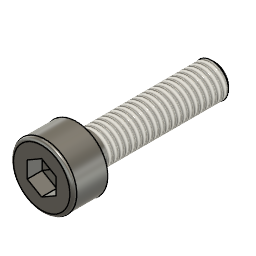
Cube_v2 (Autodesk Fusion 360 archive; units mm, degrees)
design "Hexagon Socket Head Cap Screw ISO 4762 - M3 x 12 Steel 4.6 Plain"
description: Hexagon Socket Head Cap Screw ISO 4762 - M3 x 12
part number: ISO 4762 - M3 x 12 Steel 4.6 Plain
Autodesk Fusion 360 part; units mm, degrees
(part 1 of 2)
sketch "Sketch1" plane through (0, 0, 0) normal (0, 1, 0) x (1, 0, 0)
  line L0 (-1.5, 0) -> (-1.5, 12)
  line L1 (-1.5, 12) -> (0, 12)
  line L2 (0, 12) -> (0, -3)
  line L3 (-1.5, 0) -> (-2.75, 0)
  line L4 (-2.75, 0) -> (-2.75, -3)
  line L5 (-2.75, -3) -> (0, -3)
  dimension "d9" = 3
  dimension "d106" = 3
  dimension "d107" = 12
  dimension "d116" = 5.5
  constraint perpendicular L0 L1
  constraint collinear origin L1.end L2.end
  constraint perpendicular L0 L3
  constraint coincident origin L3
  constraint vertical L2
  constraint coincident L2 L5.end
  constraint perpendicular L2 L5
  measures "d106" distance of L3 L5
  measures "d107" distance of origin L1
revolve "Revolve1" add sketch "Sketch1" angle 360 about axis through (0, 0, -12) along (0, 0, 1)
ref_plane "WorkPlane1" through (0, 0, 3) normal (0, 0, 1) x (1, 0, 0)
sketch "Sketch6" plane through (0, 0, 3) normal (0, 0, 1) x (1, 0, 0)
  line L0 (-1.25, 0.7217) -> (-1.25, -0.7217)
  line L1 (-1.25, -0.7217) -> (0, -1.4434)
  line L2 (0, -1.4434) -> (1.25, -0.7217)
  line L3 (1.25, -0.7217) -> (1.25, 0.7217)
  line L4 (1.25, 0.7217) -> (0, 1.4434)
  line L5 (0, 1.4434) -> (-1.25, 0.7217)
  dimension "d117" = 2.5
  constraint vertical L0
  measures "d117" distance of L0 L3
extrude "Extrude1" cut sketch "Sketch6" against normal blind 1.3
extrude "Extrude2" cut 1 faces at (-0.4167, 0.2406, 1.7) along direction (0, 0, -1) blind 1.3 draft -85
fillet "Fillet4" radius 0.3 1 edges at (-2.5639, 0.9944, 3)
thread "Thread3" "ISO Metric profile 3.0 M3x0.5 M3x0.5 6g" major diameter 2.927 minor diameter 2.3555 pitch 0.5 angle 60 resizes the face on face at (-1.4981, 0.0748, -8) from (0, 0, -1.25) to (0, 0, -12)
sketch "Sketch7" plane through (0, 0, 0) normal (0, 1, 0) x (1, 0, 0)
  line L0 (-1.53, 12) -> (-1.53, 11.7)
  line L1 (-1.53, 11.7) -> (-1.23, 12)
  line L2 (0, 12) -> (0, -3)
  line L3 (-1.53, 12) -> (0, 12)
  dimension "d101" = 45
  dimension "d112" = 0.3
  dimension "d113" = 1.53
  constraint coincident L2.start L3.end
  constraint perpendicular L2 L3
  constraint coincident L1.end L3
  constraint perpendicular L0 L3
  measures "d101" angle of L0 L1
  measures "d112" distance of L0.end L3
  measures "d113" distance of L0 L2.start
revolve "Revolve3" cut sketch "Sketch7" angle 360 about axis through (0, 0, 1.75) along (0, 0, 1)
equation "d9 = adsk_nomdia"
equation "adsk_nomlen = 12.00 mm"
equation "adsk_headh = 3.00 mm"
equation "adsk_headdia = 5.50 mm"
equation "adsk_nomdia = 3.00 mm"
equation "adsk_philwidth = 2.50 mm"
equation "d31 = -adsk_phildepth"
equation "adsk_phildepth = 1.30 mm"
equation "d71 = adsk_headh"
equation "d76 = -adsk_phildepth"
equation "adsk_thrlen = 10.75 mm"
equation "d86 = adsk_nomdia * 0.1"
equation "adsk_startang = 45.00 deg"
equation "d101 = adsk_startang"
equation "adsk_pitch1 = 0.50 mm"
equation "adsk_startlen = 0.30 mm"
equation "d106 = adsk_headh"
equation "d107 = adsk_nomlen"
equation "d112 = adsk_startlen"
equation "d113 = adsk_nomdia * 0.51"
equation "d115 = min(adsk_thrlen; adsk_nomlen - 0.001 mm)"
equation "d116 = adsk_headdia"
equation "d117 = adsk_philwidth"

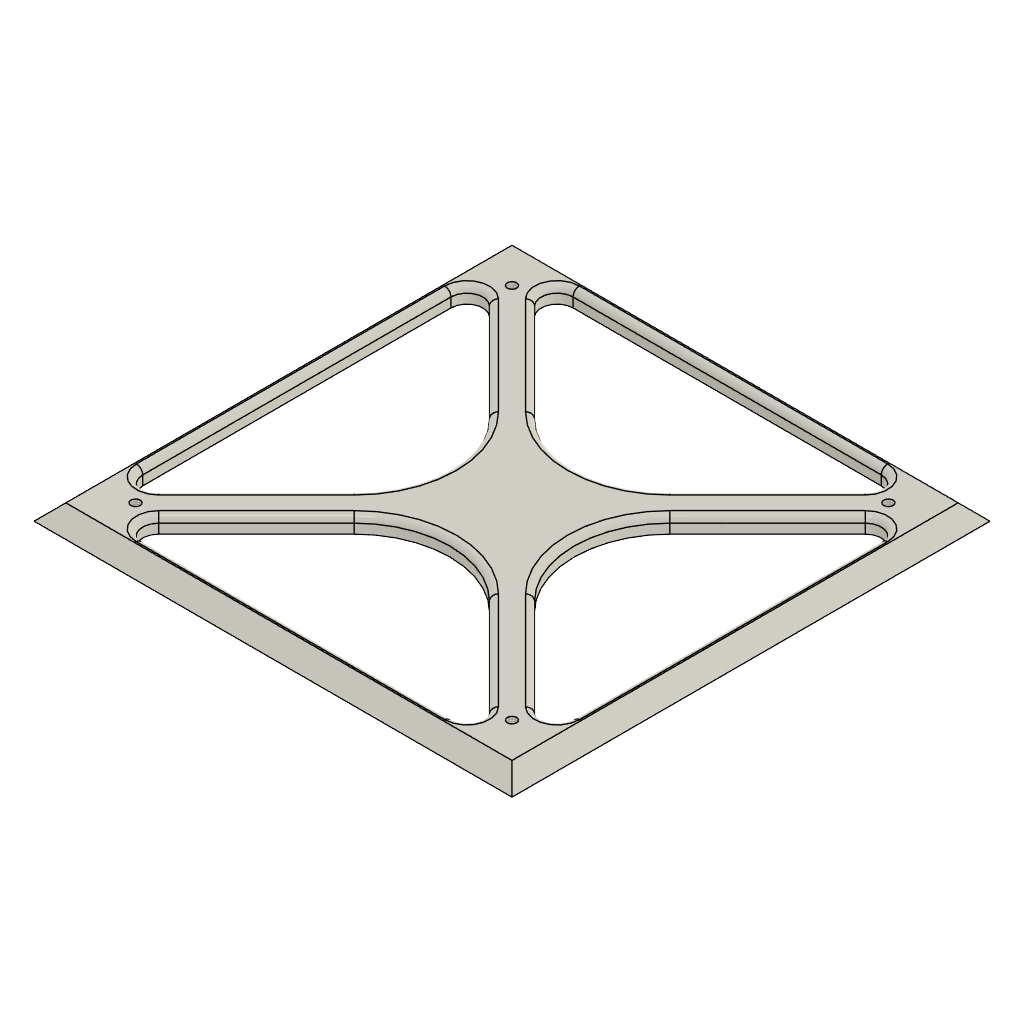
design "Cube_Bottom_Panel"
Autodesk Fusion 360 part; units mm, degrees
sketch "Sketch1" plane through (0, 0, 0) normal (0, 0, 1) x (1, 0, 0)
  line L0 (75, 75) -> (-75, 75)
  line L1 (-75, 75) -> (-75, -75)
  line L2 (-75, -75) -> (75, -75)
  line L3 (75, -75) -> (75, 75)
  line L4 (48.3579, -67.5) -> (-48.3579, -67.5)
  line L5 (-67.5, -48.3579) -> (-67.5, 48.3579)
  line L6 (-48.3579, 67.5) -> (48.3579, 67.5)
  line L7 (67.5, 48.3579) -> (67.5, -48.3579)
  line L8 (-58.9645, 51.8934) -> (-28.2843, 21.2132)
  line L9 (21.2132, -28.2843) -> (51.8934, -58.9645)
  line L10 (58.9645, -51.8934) -> (28.2843, -21.2132)
  line L11 (-21.2132, 28.2843) -> (-51.8934, 58.9645)
  line L12 (58.9645, 51.8934) -> (28.2843, 21.2132)
  line L13 (-21.2132, -28.2843) -> (-51.8934, -58.9645)
  line L14 (51.8934, 58.9645) -> (21.2132, 28.2843)
  line L15 (-28.2843, -21.2132) -> (-58.9645, -51.8934)
  arc A0 (21.2132, -28.2843) -> (-21.2132, -28.2843) centre (0, -49.4975) ccw
  arc A1 (-28.2843, -21.2132) -> (-28.2843, 21.2132) centre (-49.4975, 0) ccw
  arc A2 (-21.2132, 28.2843) -> (21.2132, 28.2843) centre (0, 49.4975) ccw
  arc A3 (28.2843, 21.2132) -> (28.2843, -21.2132) centre (49.4975, 0) ccw
  arc A4 (-48.3579, 67.5) -> (-51.8934, 58.9645) centre (-48.3579, 62.5) ccw
  arc A5 (-58.9645, 51.8934) -> (-67.5, 48.3579) centre (-62.5, 48.3579) ccw
  arc A6 (51.8934, 58.9645) -> (48.3579, 67.5) centre (48.3579, 62.5) ccw
  arc A7 (67.5, 48.3579) -> (58.9645, 51.8934) centre (62.5, 48.3579) ccw
  arc A8 (-67.5, -48.3579) -> (-58.9645, -51.8934) centre (-62.5, -48.3579) ccw
  arc A9 (-51.8934, -58.9645) -> (-48.3579, -67.5) centre (-48.3579, -62.5) ccw
  arc A10 (48.3579, -67.5) -> (51.8934, -58.9645) centre (48.3579, -62.5) ccw
  arc A11 (58.9645, -51.8934) -> (67.5, -48.3579) centre (62.5, -48.3579) ccw
  point P0 (-67.5, -67.5)
  point P1 (-67.5, 67.5)
  point P2 (67.5, 67.5)
  dimension "d1" = 150
  dimension "d2" = 150
  dimension "d3" = 135
  dimension "d4" = 135
  dimension "d9" = 30
  dimension "d10" = 30
  dimension "d11" = 30
  dimension "d12" = 30
  dimension "d13" = 5
  dimension "d14" = 5
  dimension "d15" = 5
  dimension "d16" = 5
  dimension "d17" = 5
  dimension "d18" = 5
  dimension "d19" = 5
  constraint horizontal L0
  constraint perpendicular L0 L1
  constraint parallel L0 L2
  constraint parallel L1 L3
  constraint horizontal L4
  constraint perpendicular L4 L5
  constraint parallel L4 L6
  constraint parallel L5 L7
  constraint tangent L13 A0
  constraint tangent L9 A0
  constraint tangent L15 A1
  constraint tangent L8 A1
  constraint tangent L11 A2
  constraint tangent L14 A2
  constraint tangent L10 A3
  constraint tangent L12 A3
  constraint coincident P1 L6
  constraint tangent L11 A4
  constraint tangent L6 A4
  constraint coincident P1 L5
  constraint tangent L8 A5
  constraint tangent L5 A5
  constraint coincident P2 L6
  constraint tangent L6 A6
  constraint tangent L14 A6
  constraint coincident P2 L7
  constraint tangent L12 A7
  constraint tangent L7 A7
  constraint coincident P0 L5
  constraint tangent L15 A8
  constraint tangent L5 A8
  constraint coincident P0 L4
  constraint tangent L13 A9
  constraint tangent L4 A9
  constraint equal A8 A9
  constraint tangent L4 A10
  constraint tangent L9 A10
  constraint tangent L10 A11
  constraint tangent L7 A11
  measures "d1" distance of L0.end L1.end
  measures "d2" distance of L1.end L2.end
  measures "d3" distance of P0 P1
  measures "d4" distance of P1 P2
  measures "d9" radius of A0
  measures "d10" radius of A1
  measures "d11" radius of A2
  measures "d12" radius of A3
  measures "d13" radius of A4
  measures "d14" radius of A5
  measures "d15" radius of A6
  measures "d16" radius of A7
  measures "d17" radius of A8
  measures "d18" radius of A10
  measures "d19" radius of A11
extrude "Extrude1" add sketch "Sketch1" along normal blind 5
chamfer "Chamfer1" distance 5 angle 45 4 edges at (75, 0, 5) (0, -75, 5) (-75, 0, 5) (0, 75, 5) tangent chain off
fillet "Fillet1" radius 2 24 edges at (36.5533, -43.6244, 5) (52.9773, -64.4134, 5) (0, -67.5, 5) (-52.9773, -64.4134, 5) (-36.5533, -43.6244, 5) (0, -19.4975, 5) (-64.4134, -52.9773, 5) (-67.5, 0, 5) (-64.4134, 52.9773, 5) (-43.6244, 36.5533, 5) (-19.4975, 0, 5) (-43.6244, -36.5533, 5) (-52.9773, 64.4134, 5) (0, 67.5, 5) (52.9773, 64.4134, 5) (36.5533, 43.6244, 5) (0, 19.4975, 5) (-36.5533, 43.6244, 5) (64.4134, 52.9773, 5) (67.5, 0, 5) (64.4134, -52.9773, 5) (43.6244, -36.5533, 5) (19.4975, 0, 5) (43.6244, 36.5533, 5)
sketch "Sketch4" plane through (0, 0, 0) normal (0, 0, -1) x (1, 0, 0)
  arc A0 (-21.2132, 28.2843) -> (21.2132, 28.2843) centre (0, 49.4975) ccw
  line L0 (-21.2132, 28.2843) -> (-51.8934, 58.9645)
  arc A1 (-48.3579, 67.5) -> (-51.8934, 58.9645) centre (-48.3579, 62.5) ccw
  line L1 (-48.3579, 67.5) -> (48.3579, 67.5)
  arc A2 (51.8934, 58.9645) -> (48.3579, 67.5) centre (48.3579, 62.5) ccw
  line L2 (51.8934, 58.9645) -> (21.2132, 28.2843)
  arc A3 (58.9645, -51.8934) -> (67.5, -48.3579) centre (62.5, -48.3579) ccw
  line L3 (58.9645, -51.8934) -> (28.2843, -21.2132)
  arc A4 (28.2843, 21.2132) -> (28.2843, -21.2132) centre (49.4975, 0) ccw
  line L4 (28.2843, 21.2132) -> (58.9645, 51.8934)
  arc A5 (67.5, 48.3579) -> (58.9645, 51.8934) centre (62.5, 48.3579) ccw
  line L5 (67.5, 48.3579) -> (67.5, -48.3579)
  arc A6 (-67.5, -48.3579) -> (-58.9645, -51.8934) centre (-62.5, -48.3579) ccw
  line L6 (-67.5, -48.3579) -> (-67.5, 48.3579)
  arc A7 (-58.9645, 51.8934) -> (-67.5, 48.3579) centre (-62.5, 48.3579) ccw
  line L7 (-58.9645, 51.8934) -> (-28.2843, 21.2132)
  arc A8 (-28.2843, -21.2132) -> (-28.2843, 21.2132) centre (-49.4975, 0) ccw
  line L8 (-28.2843, -21.2132) -> (-58.9645, -51.8934)
  arc A9 (21.2132, -28.2843) -> (-21.2132, -28.2843) centre (0, -49.4975) ccw
  line L9 (21.2132, -28.2843) -> (51.8934, -58.9645)
  arc A10 (48.3579, -67.5) -> (51.8934, -58.9645) centre (48.3579, -62.5) ccw
  line L10 (48.3579, -67.5) -> (-48.3579, -67.5)
  arc A11 (-51.8934, -58.9645) -> (-48.3579, -67.5) centre (-48.3579, -62.5) ccw
  line L11 (-51.8934, -58.9645) -> (-21.2132, -28.2843)
  line L12 (75, -75) -> (75, 75)
  line L13 (75, 75) -> (-75, 75)
  line L14 (-75, 75) -> (-75, -75)
  line L15 (-75, -75) -> (75, -75)
  arc A12 (-53.3076, -57.5503) -> (-48.3579, -69.5) centre (-48.3579, -62.5) ccw
  line L16 (-48.3579, -69.5) -> (48.3579, -69.5)
  arc A13 (48.3579, -69.5) -> (53.3076, -57.5503) centre (48.3579, -62.5) ccw
  line L17 (53.3076, -57.5503) -> (22.6274, -26.8701)
  arc A14 (22.6274, -26.8701) -> (-22.6274, -26.8701) centre (0, -49.4975) ccw
  line L18 (-22.6274, -26.8701) -> (-53.3076, -57.5503)
  line L19 (22.6274, 26.8701) -> (53.3076, 57.5503)
  arc A15 (53.3076, 57.5503) -> (48.3579, 69.5) centre (48.3579, 62.5) ccw
  line L20 (48.3579, 69.5) -> (-48.3579, 69.5)
  arc A16 (-48.3579, 69.5) -> (-53.3076, 57.5503) centre (-48.3579, 62.5) ccw
  line L21 (-53.3076, 57.5503) -> (-22.6274, 26.8701)
  arc A17 (-22.6274, 26.8701) -> (22.6274, 26.8701) centre (0, 49.4975) ccw
  line L22 (-70, -70) -> (-70, 70)
  line L23 (-70, 70) -> (70, 70)
  line L24 (70, 70) -> (70, -70)
  line L25 (70, -70) -> (-70, -70)
  arc A18 (-57.5503, 53.3076) -> (-69.5, 48.3579) centre (-62.5, 48.3579) ccw
  line L26 (-69.5, 48.3579) -> (-69.5, -48.3579)
  arc A19 (-69.5, -48.3579) -> (-57.5503, -53.3076) centre (-62.5, -48.3579) ccw
  line L27 (-57.5503, -53.3076) -> (-26.8701, -22.6274)
  arc A20 (-26.8701, -22.6274) -> (-26.8701, 22.6274) centre (-49.4975, 0) ccw
  line L28 (-26.8701, 22.6274) -> (-57.5503, 53.3076)
  arc A21 (57.5503, -53.3076) -> (69.5, -48.3579) centre (62.5, -48.3579) ccw
  line L29 (69.5, -48.3579) -> (69.5, 48.3579)
  arc A22 (69.5, 48.3579) -> (57.5503, 53.3076) centre (62.5, 48.3579) ccw
  line L30 (57.5503, 53.3076) -> (26.8701, 22.6274)
  arc A23 (26.8701, 22.6274) -> (26.8701, -22.6274) centre (49.4975, 0) ccw
  line L31 (26.8701, -22.6274) -> (57.5503, -53.3076)
  line L32 (70, 70) -> (59.05, 70)
  line L33 (59.05, 70) -> (59.05, 59.05)
  line L34 (-70, 70) -> (-59.05, 70) construction
  line L35 (-59.05, 70) -> (-59.05, 59.05)
  line L36 (-70, -70) -> (-59.05, -70)
  line L37 (-59.05, -70) -> (-59.05, -59.05)
  line L38 (70, -70) -> (59.05, -70)
  line L39 (59.05, -70) -> (59.05, -59.05)
  circle A24 centre (59.05, 59.05) radius 1.5
  circle A25 centre (-59.05, 59.05) radius 1.5
  circle A26 centre (-59.05, -59.05) radius 1.5
  circle A27 centre (59.05, -59.05) radius 1.5
  dimension "d25" = 10.95
  dimension "d26" = 10.95
  dimension "d27" = 10.95
  dimension "d28" = 10.95
  dimension "d29" = 10.95
  dimension "d30" = 10.95
  dimension "d31" = 10.95
  dimension "d32" = 10.95
  dimension "d33" = 3
  dimension "d34" = 3
  dimension "d35" = 3
  dimension "d36" = 3
  constraint coincident L23.end L24.start
  constraint perpendicular L24 L32
  constraint perpendicular L32 L33
  constraint coincident L22.end L23.start
  constraint perpendicular L22 L34
  constraint perpendicular L23 L35
  constraint coincident L22.start L25.end
  constraint perpendicular L22 L36
  constraint perpendicular L36 L37
  constraint coincident L24.end L25.start
  constraint perpendicular L24 L38
  constraint perpendicular L38 L39
  constraint coincident L33.end A24.centre
  constraint coincident L35.end A25.centre
  constraint coincident L37.end A26.centre
  constraint coincident L39.end A27.centre
  measures "d25" distance of L23.end L32.end
  measures "d26" distance of L32.end L33.end
  measures "d27" distance of L22.end L34.end
  measures "d28" distance of L34.end L35.end
  measures "d29" distance of L22.start L36.end
  measures "d30" distance of L36.end L37.end
  measures "d31" distance of L24.end L38.end
  measures "d32" distance of L38.end L39.end
  measures "d33" diameter of A24
  measures "d34" diameter of A25
  measures "d35" diameter of A26
  measures "d36" diameter of A27
hole "Hole1" at (-59.05, -59.05, 0) at (59.05, -59.05, 0) at (59.05, 59.05, 0) at (-59.05, 59.05, 0) direction (0, 0, 1) diameter 2.93 depth 5 tip angle 180 countersink diameter 5.2 countersink angle 90
thread "Thread1" "ISO Metric profile 3.5 M3.5x0.6 M3.5x0.6 6H" major diameter 3.5995 minor diameter 2.93 pitch 0.6 angle 60 resizes the face on face at (60.1484, 58.0806, 2.4233) on face at (-57.9516, -60.0194, 2.4233) on face at (60.1484, -60.0194, 2.4233) on face at (-57.9516, 58.0806, 2.4233)

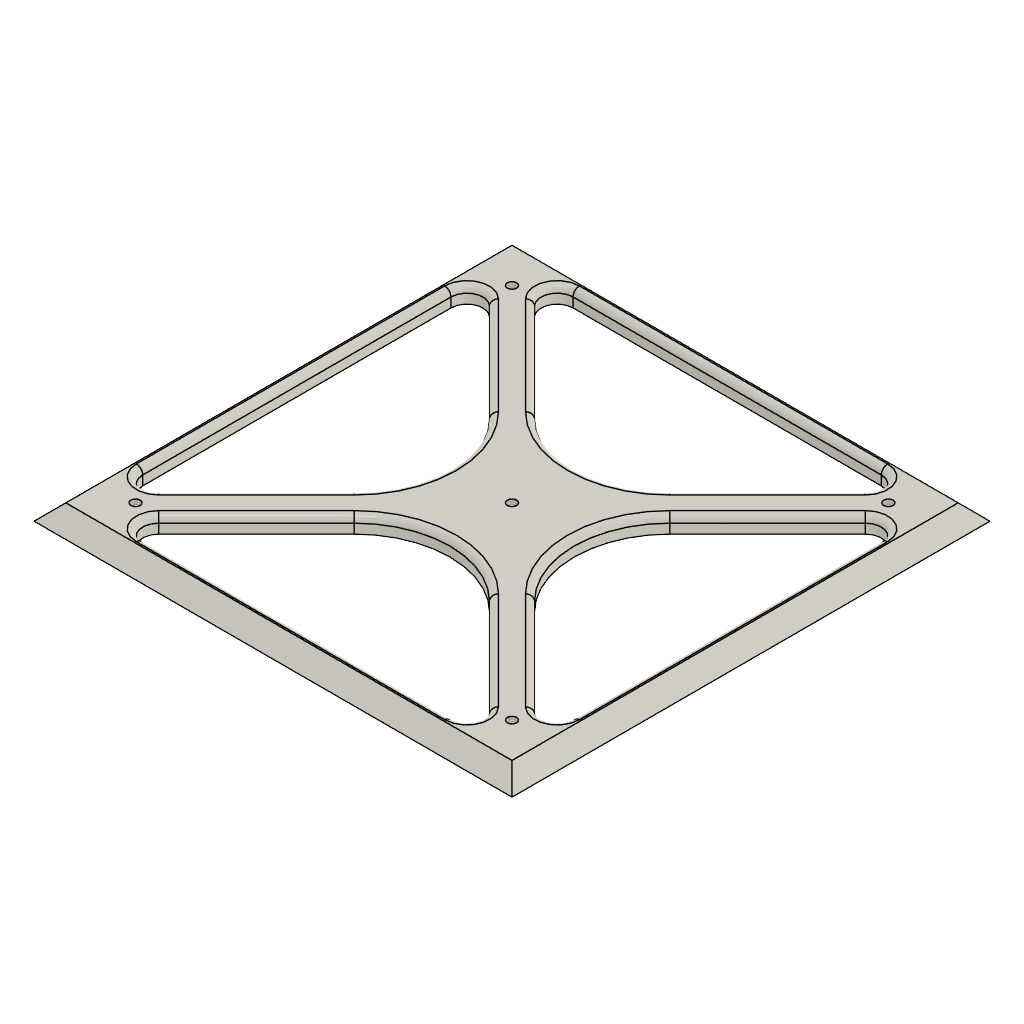
design "Cube_Top_Panel"
Autodesk Fusion 360 part; units mm, degrees
sketch "Sketch1" plane through (0, 0, 0) normal (0, 0, 1) x (1, 0, 0) in component "Cube_Bottom_Panel v4"
  line L0 (75, 75) -> (-75, 75)
  line L1 (-75, 75) -> (-75, -75)
  line L2 (-75, -75) -> (75, -75)
  line L3 (75, -75) -> (75, 75)
  line L4 (48.3579, -67.5) -> (-48.3579, -67.5)
  line L5 (-67.5, -48.3579) -> (-67.5, 48.3579)
  line L6 (-48.3579, 67.5) -> (48.3579, 67.5)
  line L7 (67.5, 48.3579) -> (67.5, -48.3579)
  line L8 (-58.9645, 51.8934) -> (-28.2843, 21.2132)
  line L9 (21.2132, -28.2843) -> (51.8934, -58.9645)
  line L10 (58.9645, -51.8934) -> (28.2843, -21.2132)
  line L11 (-21.2132, 28.2843) -> (-51.8934, 58.9645)
  line L12 (58.9645, 51.8934) -> (28.2843, 21.2132)
  line L13 (-21.2132, -28.2843) -> (-51.8934, -58.9645)
  line L14 (51.8934, 58.9645) -> (21.2132, 28.2843)
  line L15 (-28.2843, -21.2132) -> (-58.9645, -51.8934)
  arc A0 (21.2132, -28.2843) -> (-21.2132, -28.2843) centre (0, -49.4975) ccw
  arc A1 (-28.2843, -21.2132) -> (-28.2843, 21.2132) centre (-49.4975, 0) ccw
  arc A2 (-21.2132, 28.2843) -> (21.2132, 28.2843) centre (0, 49.4975) ccw
  arc A3 (28.2843, 21.2132) -> (28.2843, -21.2132) centre (49.4975, 0) ccw
  arc A4 (-48.3579, 67.5) -> (-51.8934, 58.9645) centre (-48.3579, 62.5) ccw
  arc A5 (-58.9645, 51.8934) -> (-67.5, 48.3579) centre (-62.5, 48.3579) ccw
  arc A6 (51.8934, 58.9645) -> (48.3579, 67.5) centre (48.3579, 62.5) ccw
  arc A7 (67.5, 48.3579) -> (58.9645, 51.8934) centre (62.5, 48.3579) ccw
  arc A8 (-67.5, -48.3579) -> (-58.9645, -51.8934) centre (-62.5, -48.3579) ccw
  arc A9 (-51.8934, -58.9645) -> (-48.3579, -67.5) centre (-48.3579, -62.5) ccw
  arc A10 (48.3579, -67.5) -> (51.8934, -58.9645) centre (48.3579, -62.5) ccw
  arc A11 (58.9645, -51.8934) -> (67.5, -48.3579) centre (62.5, -48.3579) ccw
  point P0 (-67.5, -67.5)
  point P1 (-67.5, 67.5)
  point P2 (67.5, 67.5)
  dimension "d1" = 150
  dimension "d2" = 150
  dimension "d3" = 135
  dimension "d4" = 135
  dimension "d9" = 30
  dimension "d10" = 30
  dimension "d11" = 30
  dimension "d12" = 30
  dimension "d13" = 5
  dimension "d14" = 5
  dimension "d15" = 5
  dimension "d16" = 5
  dimension "d17" = 5
  dimension "d18" = 5
  dimension "d19" = 5
  constraint horizontal L0
  constraint perpendicular L0 L1
  constraint parallel L0 L2
  constraint parallel L1 L3
  constraint horizontal L4
  constraint perpendicular L4 L5
  constraint parallel L4 L6
  constraint parallel L5 L7
  constraint tangent L13 A0
  constraint tangent L9 A0
  constraint tangent L15 A1
  constraint tangent L8 A1
  constraint tangent L11 A2
  constraint tangent L14 A2
  constraint tangent L10 A3
  constraint tangent L12 A3
  constraint coincident P1 L6
  constraint tangent L11 A4
  constraint tangent L6 A4
  constraint coincident P1 L5
  constraint tangent L8 A5
  constraint tangent L5 A5
  constraint coincident P2 L6
  constraint tangent L6 A6
  constraint tangent L14 A6
  constraint coincident P2 L7
  constraint tangent L12 A7
  constraint tangent L7 A7
  constraint coincident P0 L5
  constraint tangent L15 A8
  constraint tangent L5 A8
  constraint coincident P0 L4
  constraint tangent L13 A9
  constraint tangent L4 A9
  constraint equal A8 A9
  constraint tangent L4 A10
  constraint tangent L9 A10
  constraint tangent L10 A11
  constraint tangent L7 A11
  measures "d1" distance of L0.end L1.end
  measures "d2" distance of L1.end L2.end
  measures "d3" distance of P0 P1
  measures "d4" distance of P1 P2
  measures "d9" radius of A0
  measures "d10" radius of A1
  measures "d11" radius of A2
  measures "d12" radius of A3
  measures "d13" radius of A4
  measures "d14" radius of A5
  measures "d15" radius of A6
  measures "d16" radius of A7
  measures "d17" radius of A8
  measures "d18" radius of A10
  measures "d19" radius of A11
extrude "Extrude1" add sketch "Sketch1" along normal blind 5 in component "Cube_Bottom_Panel v4"
chamfer "Chamfer1" distance 5 angle 45 4 edges at (75, 0, 5) (0, -75, 5) (-75, 0, 5) (0, 75, 5) tangent chain off in component "Cube_Bottom_Panel v4"
fillet "Fillet1" radius 2 24 edges at (36.5533, -43.6244, 5) (52.9773, -64.4134, 5) (0, -67.5, 5) (-52.9773, -64.4134, 5) (-36.5533, -43.6244, 5) (0, -19.4975, 5) (-64.4134, -52.9773, 5) (-67.5, 0, 5) (-64.4134, 52.9773, 5) (-43.6244, 36.5533, 5) (-19.4975, 0, 5) (-43.6244, -36.5533, 5) (-52.9773, 64.4134, 5) (0, 67.5, 5) (52.9773, 64.4134, 5) (36.5533, 43.6244, 5) (0, 19.4975, 5) (-36.5533, 43.6244, 5) (64.4134, 52.9773, 5) (67.5, 0, 5) (64.4134, -52.9773, 5) (43.6244, -36.5533, 5) (19.4975, 0, 5) (43.6244, 36.5533, 5) in component "Cube_Bottom_Panel v4"
sketch "Sketch4" plane through (0, 0, 0) normal (0, 0, -1) x (1, 0, 0) in component "Cube_Bottom_Panel v4"
  arc A0 (-21.2132, 28.2843) -> (21.2132, 28.2843) centre (0, 49.4975) ccw
  line L0 (-21.2132, 28.2843) -> (-51.8934, 58.9645)
  arc A1 (-48.3579, 67.5) -> (-51.8934, 58.9645) centre (-48.3579, 62.5) ccw
  line L1 (-48.3579, 67.5) -> (48.3579, 67.5)
  arc A2 (51.8934, 58.9645) -> (48.3579, 67.5) centre (48.3579, 62.5) ccw
  line L2 (51.8934, 58.9645) -> (21.2132, 28.2843)
  arc A3 (58.9645, -51.8934) -> (67.5, -48.3579) centre (62.5, -48.3579) ccw
  line L3 (58.9645, -51.8934) -> (28.2843, -21.2132)
  arc A4 (28.2843, 21.2132) -> (28.2843, -21.2132) centre (49.4975, 0) ccw
  line L4 (28.2843, 21.2132) -> (58.9645, 51.8934)
  arc A5 (67.5, 48.3579) -> (58.9645, 51.8934) centre (62.5, 48.3579) ccw
  line L5 (67.5, 48.3579) -> (67.5, -48.3579)
  arc A6 (-67.5, -48.3579) -> (-58.9645, -51.8934) centre (-62.5, -48.3579) ccw
  line L6 (-67.5, -48.3579) -> (-67.5, 48.3579)
  arc A7 (-58.9645, 51.8934) -> (-67.5, 48.3579) centre (-62.5, 48.3579) ccw
  line L7 (-58.9645, 51.8934) -> (-28.2843, 21.2132)
  arc A8 (-28.2843, -21.2132) -> (-28.2843, 21.2132) centre (-49.4975, 0) ccw
  line L8 (-28.2843, -21.2132) -> (-58.9645, -51.8934)
  arc A9 (21.2132, -28.2843) -> (-21.2132, -28.2843) centre (0, -49.4975) ccw
  line L9 (21.2132, -28.2843) -> (51.8934, -58.9645)
  arc A10 (48.3579, -67.5) -> (51.8934, -58.9645) centre (48.3579, -62.5) ccw
  line L10 (48.3579, -67.5) -> (-48.3579, -67.5)
  arc A11 (-51.8934, -58.9645) -> (-48.3579, -67.5) centre (-48.3579, -62.5) ccw
  line L11 (-51.8934, -58.9645) -> (-21.2132, -28.2843)
  line L12 (75, -75) -> (75, 75)
  line L13 (75, 75) -> (-75, 75)
  line L14 (-75, 75) -> (-75, -75)
  line L15 (-75, -75) -> (75, -75)
  arc A12 (-53.3076, -57.5503) -> (-48.3579, -69.5) centre (-48.3579, -62.5) ccw
  line L16 (-48.3579, -69.5) -> (48.3579, -69.5)
  arc A13 (48.3579, -69.5) -> (53.3076, -57.5503) centre (48.3579, -62.5) ccw
  line L17 (53.3076, -57.5503) -> (22.6274, -26.8701)
  arc A14 (22.6274, -26.8701) -> (-22.6274, -26.8701) centre (0, -49.4975) ccw
  line L18 (-22.6274, -26.8701) -> (-53.3076, -57.5503)
  line L19 (22.6274, 26.8701) -> (53.3076, 57.5503)
  arc A15 (53.3076, 57.5503) -> (48.3579, 69.5) centre (48.3579, 62.5) ccw
  line L20 (48.3579, 69.5) -> (-48.3579, 69.5)
  arc A16 (-48.3579, 69.5) -> (-53.3076, 57.5503) centre (-48.3579, 62.5) ccw
  line L21 (-53.3076, 57.5503) -> (-22.6274, 26.8701)
  arc A17 (-22.6274, 26.8701) -> (22.6274, 26.8701) centre (0, 49.4975) ccw
  line L22 (-70, -70) -> (-70, 70)
  line L23 (-70, 70) -> (70, 70)
  line L24 (70, 70) -> (70, -70)
  line L25 (70, -70) -> (-70, -70)
  arc A18 (-57.5503, 53.3076) -> (-69.5, 48.3579) centre (-62.5, 48.3579) ccw
  line L26 (-69.5, 48.3579) -> (-69.5, -48.3579)
  arc A19 (-69.5, -48.3579) -> (-57.5503, -53.3076) centre (-62.5, -48.3579) ccw
  line L27 (-57.5503, -53.3076) -> (-26.8701, -22.6274)
  arc A20 (-26.8701, -22.6274) -> (-26.8701, 22.6274) centre (-49.4975, 0) ccw
  line L28 (-26.8701, 22.6274) -> (-57.5503, 53.3076)
  arc A21 (57.5503, -53.3076) -> (69.5, -48.3579) centre (62.5, -48.3579) ccw
  line L29 (69.5, -48.3579) -> (69.5, 48.3579)
  arc A22 (69.5, 48.3579) -> (57.5503, 53.3076) centre (62.5, 48.3579) ccw
  line L30 (57.5503, 53.3076) -> (26.8701, 22.6274)
  arc A23 (26.8701, 22.6274) -> (26.8701, -22.6274) centre (49.4975, 0) ccw
  line L31 (26.8701, -22.6274) -> (57.5503, -53.3076)
  line L32 (70, 70) -> (59.05, 70)
  line L33 (59.05, 70) -> (59.05, 59.05)
  line L34 (-70, 70) -> (-59.05, 70) construction
  line L35 (-59.05, 70) -> (-59.05, 59.05)
  line L36 (-70, -70) -> (-59.05, -70)
  line L37 (-59.05, -70) -> (-59.05, -59.05)
  line L38 (70, -70) -> (59.05, -70)
  line L39 (59.05, -70) -> (59.05, -59.05)
  circle A24 centre (59.05, 59.05) radius 1.5
  circle A25 centre (-59.05, 59.05) radius 1.5
  circle A26 centre (-59.05, -59.05) radius 1.5
  circle A27 centre (59.05, -59.05) radius 1.5
  dimension "d25" = 10.95
  dimension "d26" = 10.95
  dimension "d27" = 10.95
  dimension "d28" = 10.95
  dimension "d29" = 10.95
  dimension "d30" = 10.95
  dimension "d31" = 10.95
  dimension "d32" = 10.95
  dimension "d33" = 3
  dimension "d34" = 3
  dimension "d35" = 3
  dimension "d36" = 3
  constraint coincident L23.end L24.start
  constraint perpendicular L24 L32
  constraint perpendicular L32 L33
  constraint coincident L22.end L23.start
  constraint perpendicular L22 L34
  constraint perpendicular L23 L35
  constraint coincident L22.start L25.end
  constraint perpendicular L22 L36
  constraint perpendicular L36 L37
  constraint coincident L24.end L25.start
  constraint perpendicular L24 L38
  constraint perpendicular L38 L39
  constraint coincident L33.end A24.centre
  constraint coincident L35.end A25.centre
  constraint coincident L37.end A26.centre
  constraint coincident L39.end A27.centre
  measures "d25" distance of L23.end L32.end
  measures "d26" distance of L32.end L33.end
  measures "d27" distance of L22.end L34.end
  measures "d28" distance of L34.end L35.end
  measures "d29" distance of L22.start L36.end
  measures "d30" distance of L36.end L37.end
  measures "d31" distance of L24.end L38.end
  measures "d32" distance of L38.end L39.end
  measures "d33" diameter of A24
  measures "d34" diameter of A25
  measures "d35" diameter of A26
  measures "d36" diameter of A27
hole "Hole1" at (-59.05, -59.05, 0) at (59.05, -59.05, 0) at (59.05, 59.05, 0) at (-59.05, 59.05, 0) direction (0, 0, 1) diameter 2.93 depth 5 tip angle 180 countersink diameter 5.2 countersink angle 90 in component "Cube_Bottom_Panel v4"
thread "Thread1" "ISO Metric profile 3.5 M3.5x0.6 M3.5x0.6 6H" major diameter 3.5995 minor diameter 2.93 pitch 0.6 angle 60 resizes the face on face at (60.1484, 58.0806, 2.4233) on face at (-57.9516, -60.0194, 2.4233) on face at (60.1484, -60.0194, 2.4233) on face at (-57.9516, 58.0806, 2.4233) in component "Cube_Bottom_Panel v4"
sketch "Sketch2" plane through (0, 0, 0) normal (0, 0, -1) x (1, 0, 0)
  line L0 (75, -75) -> (75, 75)
  line L1 (75, 75) -> (-75, 75)
  line L2 (-75, 75) -> (-75, -75)
  line L3 (-75, -75) -> (75, -75)
  arc A0 (58.9645, -51.8934) -> (67.5, -48.3579) centre (62.5, -48.3579) ccw
  line L4 (58.9645, -51.8934) -> (28.2843, -21.2132)
  arc A1 (28.2843, 21.2132) -> (28.2843, -21.2132) centre (49.4975, 0) ccw
  line L5 (28.2843, 21.2132) -> (58.9645, 51.8934)
  arc A2 (67.5, 48.3579) -> (58.9645, 51.8934) centre (62.5, 48.3579) ccw
  line L6 (67.5, 48.3579) -> (67.5, -48.3579)
  arc A3 (-67.5, -48.3579) -> (-58.9645, -51.8934) centre (-62.5, -48.3579) ccw
  line L7 (-67.5, -48.3579) -> (-67.5, 48.3579)
  arc A4 (-58.9645, 51.8934) -> (-67.5, 48.3579) centre (-62.5, 48.3579) ccw
  line L8 (-58.9645, 51.8934) -> (-28.2843, 21.2132)
  arc A5 (-28.2843, -21.2132) -> (-28.2843, 21.2132) centre (-49.4975, 0) ccw
  line L9 (-28.2843, -21.2132) -> (-58.9645, -51.8934)
  arc A6 (21.2132, -28.2843) -> (-21.2132, -28.2843) centre (0, -49.4975) ccw
  line L10 (21.2132, -28.2843) -> (51.8934, -58.9645)
  arc A7 (48.3579, -67.5) -> (51.8934, -58.9645) centre (48.3579, -62.5) ccw
  line L11 (48.3579, -67.5) -> (-48.3579, -67.5)
  arc A8 (-51.8934, -58.9645) -> (-48.3579, -67.5) centre (-48.3579, -62.5) ccw
  line L12 (-51.8934, -58.9645) -> (-21.2132, -28.2843)
  arc A9 (-21.2132, 28.2843) -> (21.2132, 28.2843) centre (0, 49.4975) ccw
  line L13 (-21.2132, 28.2843) -> (-51.8934, 58.9645)
  arc A10 (-48.3579, 67.5) -> (-51.8934, 58.9645) centre (-48.3579, 62.5) ccw
  line L14 (-48.3579, 67.5) -> (48.3579, 67.5)
  arc A11 (51.8934, 58.9645) -> (48.3579, 67.5) centre (48.3579, 62.5) ccw
  line L15 (51.8934, 58.9645) -> (21.2132, 28.2843)
  circle A12 centre (-59.05, -59.05) radius 2.6
  circle A13 centre (59.05, 59.05) radius 2.6
  circle A14 centre (-59.05, 59.05) radius 2.6
  circle A15 centre (59.05, -59.05) radius 2.6
sketch "Sketch3" plane through (0, 0, 0) normal (0, 0, -1) x (1, 0, 0)
  line L0 (75, -75) -> (75, 75)
  line L1 (75, 75) -> (-75, 75)
  line L2 (-75, 75) -> (-75, -75)
  line L3 (-75, -75) -> (75, -75)
  arc A0 (58.9645, -51.8934) -> (67.5, -48.3579) centre (62.5, -48.3579) ccw
  line L4 (58.9645, -51.8934) -> (28.2843, -21.2132)
  arc A1 (28.2843, 21.2132) -> (28.2843, -21.2132) centre (49.4975, 0) ccw
  line L5 (28.2843, 21.2132) -> (58.9645, 51.8934)
  arc A2 (67.5, 48.3579) -> (58.9645, 51.8934) centre (62.5, 48.3579) ccw
  line L6 (67.5, 48.3579) -> (67.5, -48.3579)
  arc A3 (-67.5, -48.3579) -> (-58.9645, -51.8934) centre (-62.5, -48.3579) ccw
  line L7 (-67.5, -48.3579) -> (-67.5, 48.3579)
  arc A4 (-58.9645, 51.8934) -> (-67.5, 48.3579) centre (-62.5, 48.3579) ccw
  line L8 (-58.9645, 51.8934) -> (-28.2843, 21.2132)
  arc A5 (-28.2843, -21.2132) -> (-28.2843, 21.2132) centre (-49.4975, 0) ccw
  line L9 (-28.2843, -21.2132) -> (-58.9645, -51.8934)
  arc A6 (21.2132, -28.2843) -> (-21.2132, -28.2843) centre (0, -49.4975) ccw
  line L10 (21.2132, -28.2843) -> (51.8934, -58.9645)
  arc A7 (48.3579, -67.5) -> (51.8934, -58.9645) centre (48.3579, -62.5) ccw
  line L11 (48.3579, -67.5) -> (-48.3579, -67.5)
  arc A8 (-51.8934, -58.9645) -> (-48.3579, -67.5) centre (-48.3579, -62.5) ccw
  line L12 (-51.8934, -58.9645) -> (-21.2132, -28.2843)
  arc A9 (-21.2132, 28.2843) -> (21.2132, 28.2843) centre (0, 49.4975) ccw
  line L13 (-21.2132, 28.2843) -> (-51.8934, 58.9645)
  arc A10 (-48.3579, 67.5) -> (-51.8934, 58.9645) centre (-48.3579, 62.5) ccw
  line L14 (-48.3579, 67.5) -> (48.3579, 67.5)
  arc A11 (51.8934, 58.9645) -> (48.3579, 67.5) centre (48.3579, 62.5) ccw
  line L15 (51.8934, 58.9645) -> (21.2132, 28.2843)
  circle A12 centre (-59.05, -59.05) radius 2.6
  circle A13 centre (59.05, 59.05) radius 2.6
  circle A14 centre (-59.05, 59.05) radius 2.6
  circle A15 centre (59.05, -59.05) radius 2.6
hole "Hole2" at (0, 0, 0) direction (0, 0, 1) diameter 2.93 depth 5 tip angle 180 counterbore diameter 5.2 counterbore depth 2.4 in component "Cube_Bottom_Panel v4"
thread "Thread2" "ISO Metric profile 3.5 M3.5x0.6 M3.5x0.6 6H" thread offset 0 thread depth 7.4 in component "Cube_Bottom_Panel v4"
component "Cube_Bottom_Panel v4" placed x (1, 0, 0) y (0, 1, 0) z (0, 0, 1) at (0, 0, 0)

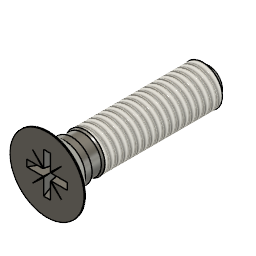
design "Countersunk Head Screw ISO 7046-2 - M3 x 12 - Z Steel 4.6 Plain"
description: Countersunk Head Screw ISO 7046-2 - M3 x 12 - Z
part number: ISO 7046-2 - M3x12 - Z Steel 4.6 Plain
Autodesk Fusion 360 part; units mm, degrees
sketch "Sketch1" plane through (0, 0, 0) normal (0, 1, 0) x (1, 0, 0)
  line L0 (0, -2.84) -> (-2.75, -2.84)
  line L1 (-2.75, -2.84) -> (-2.75, -2.75)
  line L2 (-2.75, -2.75) -> (-1.5, -1.5)
  line L3 (-1.5, 0.06) -> (-1.5, 9.16)
  line L4 (-1.5, 9.16) -> (0, 9.16)
  line L5 (0, 9.16) -> (0, -2.84)
  line L6 (-1.5, 0.06) -> (-1.375, -0.19)
  line L7 (-1.375, -0.19) -> (-1.375, -1)
  line L8 (-1.5, -1.5) -> (-1.5, -1)
  line L9 (-1.5, -1) -> (-1.375, -1)
  dimension "d9" = 3
  dimension "d11" = 5.5
  dimension "d89" = 2.75
  dimension "d90" = 3
  dimension "d91" = 0.5
  dimension "d93" = 9.1
  dimension "d120" = 12
  dimension "d126" = 45
  dimension "d127" = 9.35
  dimension "d131" = 0.09
  constraint perpendicular L0 L1
  constraint perpendicular L3 L4
  constraint perpendicular L0 L5
  constraint collinear origin L0.start L4.end
  constraint vertical L7
  constraint coincident origin L2
  constraint horizontal L9
  measures "d91" distance of L2.end L9
  measures "d93" distance of L4 L3.start
  measures "d120" distance of L0 L4
  measures "d126" angle of L2 L5
  measures "d127" distance of L4 L6.end
  measures "d131" distance of L0 L1.end
revolve "Revolve1" add sketch "Sketch1" angle 360 about axis through (0, 0, -9.16) along (0, 0, 1) makes body 1
sketch "Sketch7" plane through (0, 0, 2.84) normal (0, 0, 1) x (1, 0, 0)
  circle A0 centre (0, 0) radius 2.75
  line L0 (0.3, 0.3) -> (0.3, -0.3)
  line L1 (-0.3, 0.3) -> (0.3, 0.3)
  line L2 (-0.3, -0.3) -> (-0.3, 0.3)
  line L3 (0.3, -0.3) -> (-0.3, -0.3)
  dimension "d129" = 360
  dimension "d130" = 0.6
  constraint vertical L0
  constraint coincident L0.start L1.end
  measures "d130" distance of L1 L3
extrude "Extrude4" add sketch "Sketch7" against normal blind 1.608 draft -10 separate body contours L0 L1 L2 L3 makes body 2
sketch "Sketch2" plane through (0, 0, 2.84) normal (0, 0, 1) x (1, 0, 0)
  circle A0 centre (0, 0) radius 2.75
  line L0 (-0.25, 0.25) -> (-1.5, 0.25)
  line L1 (-1.5, 0.25) -> (-1.5, -0.25)
  line L2 (-1.5, -0.25) -> (-0.25, -0.25)
  line L3 (-0.25, -0.25) -> (-0.25, -1.5)
  line L4 (-0.25, -1.5) -> (0.25, -1.5)
  line L5 (0.25, -1.5) -> (0.25, -0.25)
  line L6 (0.25, -0.25) -> (1.5, -0.25)
  line L7 (1.5, -0.25) -> (1.5, 0.25)
  line L8 (1.5, 0.25) -> (0.25, 0.25)
  line L9 (0.25, 0.25) -> (0.25, 1.5)
  line L10 (0.25, 1.5) -> (-0.25, 1.5)
  line L11 (-0.25, 1.5) -> (-0.25, 0.25)
  dimension "d117" = 360
  dimension "d123" = 0.5
  dimension "d124" = 3
  constraint perpendicular L0 L1
  constraint vertical L0.start L2.end
  constraint horizontal L2
  constraint coincident L0.start L11.end
  measures "d123" distance of L0 L2
  measures "d124" distance of L3.end L10
extrude "Extrude1" add sketch "Sketch2" against normal blind 2.01 draft -4 separate body contours L0 L1 L2 L3 L4 L5 L6 L7 L8 L9 L10 L11 makes body 3
draft "Draft1" angle -30 neutral plane through (0, 0, 2.84) pull (0, 0, 1) 4 faces at (1.4531, 0.0365, 2.17) (0.0365, 1.4531, 2.17) (-1.4531, 0.0365, 2.17) (0.0365, -1.4531, 2.17) on bodies 3
combine "Combine1" operation cut target body 1 tool bodies 2 3
sketch "Sketch6" plane through (0, 0, 2.84) normal (0, 0, 1) x (1, 0, 0)
  circle A0 centre (0, 0) radius 1.5207 construction
  line L0 (0, 0) -> (-1.0753, 1.0753) construction
  line L1 (-1.0753, 1.0753) -> (-0.25, 0.3)
  line L2 (-0.25, 0.3) -> (-0.3, 0.25)
  line L3 (-0.3, 0.25) -> (-1.0753, 1.0753)
  point P0 (-0.25, 1.5)
  point P1 (-0.25, 1.5)
  point P2 (-0.3, 0.3)
  point P3 (-0.25, 0.3)
  point P4 (-0.3, 0.25)
  constraint coincident A0.centre L0.start
  constraint coincident A0 P1
  constraint coincident A0 L0.end
  constraint coincident L0 P2
  constraint perpendicular L0 L2
  constraint coincident P1 P0
  constraint coincident P3 L1.end
  constraint coincident P4 L2.end
extrude "Extrude2" cut sketch "Sketch6" against normal blind 1.65 draft -30 bodies 1
pattern_circular "C-Pattern1" count 4 over 360 about axis through (0, 0, 1.75) along (0, 0, 1) of "Extrude2"
thread "Thread2" "ISO Metric profile 3.0 M3x0.5 M3x0.5 6g" major diameter 2.927 minor diameter 2.3555 pitch 0.5 angle 60 resizes the face on face at (-1.4981, 0.0748, -3.0933) on bodies 1
sketch "Sketch8" plane through (0, 0, 0) normal (0, 1, 0) x (1, 0, 0)
  line L0 (-1, 9.16) -> (-1.53, 9.16)
  line L1 (-1.53, 9.16) -> (-1.53, 8.63)
  line L2 (-1.53, 8.63) -> (-1, 9.16)
  point P0 (0, 9.16)
  dimension "d108" = 45
  dimension "d110" = 1.53
  dimension "d125" = 0.53
  constraint horizontal L0
  constraint perpendicular L0 L1
  constraint coincident L0 P0
  measures "d108" angle of L1 L2
  measures "d110" distance of L1 P0
  measures "d125" distance of L0 L1.end
revolve "Revolve3" cut sketch "Sketch8" angle 360 about axis through (0, 0, -9.16) along (0, 0, 1) bodies 1
equation "d9 = adsk_nomdia"
equation "d11 = adsk_headdia"
equation "adsk_nomlen = 12.00 mm"
equation "adsk_headh = 1.65 mm"
equation "adsk_headdia = 5.50 mm"
equation "adsk_nomdia = 3.00 mm"
equation "adsk_headang = 90.00 deg"
equation "adsk_phildia = 3.00 mm"
equation "d31 = -adsk_phildepth"
equation "adsk_philwidth = adsk_phildia / 6"
equation "adsk_phildepth = 2.01 mm"
equation "d61 = -adsk_headh"
equation "d68 = -adsk_phildepth * 0.8"
equation "adsk_startlen = adsk_pitch1"
equation "adsk_shnkdia = adsk_nomdia - 0.5 * adsk_pitch1"
equation "d89 = adsk_shnkdia"
equation "d90 = adsk_nomdia"
equation "d91 = adsk_pitch1"
equation "d93 = adsk_thrlen"
equation "adsk_thrlen = 9.10 mm"
equation "adsk_pitch1 = 0.50 mm"
equation "adsk_thrrun = 0.25 mm"
equation "d102 = ( adsk_nomdia / 2 ) * tan(90 deg - adsk_headang / 2) + adsk_headh"
equation "d110 = adsk_nomdia * 0.51"
equation "d120 = adsk_nomlen"
equation "d123 = adsk_philwidth"
equation "d124 = adsk_phildia"
equation "d125 = adsk_startlen + adsk_nomdia * 0.01"
equation "d126 = adsk_headang * 0.5"
equation "d127 = adsk_thrrun + adsk_thrlen"
equation "d130 = adsk_philwidth * 1.2"
equation "d131 = 0.03 * adsk_nomdia"

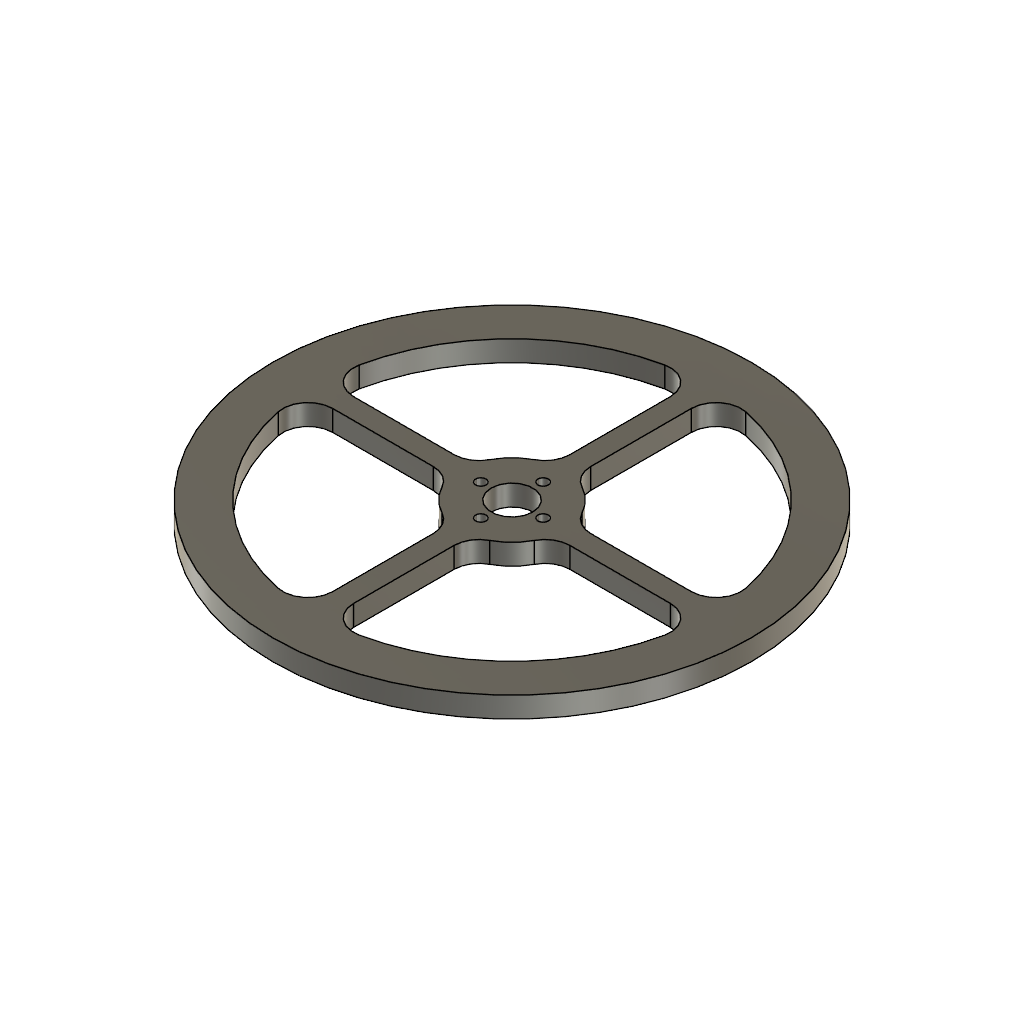
design "Cube_Reaction_Wheel_V2"
Autodesk Fusion 360 part; units mm, degrees
sketch "Sketch1" plane through (0, 0, 0) normal (0, 0, 1) x (1, 0, 0)
  circle A0 centre (0, 0) radius 57.5
  circle A1 centre (0, 0) radius 5
  line L0 (-2.5, -40.6202) -> (-2.5, -16.4317)
  line L1 (-2.5, 16.4317) -> (-2.5, 40.6202)
  line L2 (2.5, -40.6202) -> (2.5, -16.4317)
  line L3 (2.5, 16.4317) -> (2.5, 40.6202)
  arc A2 (-9.7289, 46.493) -> (-46.493, 9.7289) centre (0, 0) ccw
  arc A3 (-46.493, -9.7289) -> (-9.7289, -46.493) centre (0, 0) ccw
  arc A4 (-5.7432, 11.1025) -> (-11.1025, 5.7432) centre (0, 0) ccw
  arc A5 (-11.1025, -5.7432) -> (-5.7432, -11.1025) centre (0, 0) ccw
  arc A6 (9.7289, -46.493) -> (46.493, -9.7289) centre (0, 0) ccw
  arc A7 (46.493, 9.7289) -> (9.7289, 46.493) centre (0, 0) ccw
  line L4 (-40.6202, 2.5) -> (-16.4317, 2.5)
  line L5 (16.4317, 2.5) -> (40.6202, 2.5)
  line L6 (-40.6202, -2.5) -> (-16.4317, -2.5)
  line L7 (16.4317, -2.5) -> (40.6202, -2.5)
  arc A8 (5.7432, -11.1025) -> (11.1025, -5.7432) centre (0, 0) ccw
  arc A9 (11.1025, 5.7432) -> (5.7432, 11.1025) centre (0, 0) ccw
  arc A10 (-46.493, 9.7289) -> (-40.6202, 2.5) centre (-40.6202, 8.5) ccw
  arc A11 (-40.6202, -2.5) -> (-46.493, -9.7289) centre (-40.6202, -8.5) ccw
  arc A12 (-2.5, 40.6202) -> (-9.7289, 46.493) centre (-8.5, 40.6202) ccw
  arc A13 (9.7289, 46.493) -> (2.5, 40.6202) centre (8.5, 40.6202) ccw
  arc A14 (40.6202, 2.5) -> (46.493, 9.7289) centre (40.6202, 8.5) ccw
  arc A15 (46.493, -9.7289) -> (40.6202, -2.5) centre (40.6202, -8.5) ccw
  arc A16 (2.5, -40.6202) -> (9.7289, -46.493) centre (8.5, -40.6202) ccw
  arc A17 (-9.7289, -46.493) -> (-2.5, -40.6202) centre (-8.5, -40.6202) ccw
  arc A18 (-11.1025, -5.7432) -> (-16.4317, -2.5) centre (-16.4317, -8.5) ccw
  arc A19 (-2.5, -16.4317) -> (-5.7432, -11.1025) centre (-8.5, -16.4317) ccw
  arc A20 (5.7432, -11.1025) -> (2.5, -16.4317) centre (8.5, -16.4317) ccw
  arc A21 (16.4317, -2.5) -> (11.1025, -5.7432) centre (16.4317, -8.5) ccw
  arc A22 (-16.4317, 2.5) -> (-11.1025, 5.7432) centre (-16.4317, 8.5) ccw
  arc A23 (-5.7432, 11.1025) -> (-2.5, 16.4317) centre (-8.5, 16.4317) ccw
  arc A24 (2.5, 16.4317) -> (5.7432, 11.1025) centre (8.5, 16.4317) ccw
  arc A25 (11.1025, 5.7432) -> (16.4317, 2.5) centre (16.4317, 8.5) ccw
  circle A26 centre (0, 7.5) radius 1.25
  circle A27 centre (-7.5, 0) radius 1.25
  circle A28 centre (0, -7.5) radius 1.25
  circle A29 centre (7.5, 0) radius 1.25
  dimension "d1" = 115
  dimension "d2" = 95
  dimension "d3" = 10
  dimension "d4" = 25
  dimension "d15" = 6
  dimension "d16" = 6
  dimension "d17" = 6
  dimension "d18" = 6
  dimension "d19" = 6
  dimension "d20" = 6
  dimension "d21" = 6
  dimension "d22" = 6
  dimension "d23" = 6
  dimension "d24" = 6
  dimension "d25" = 6
  dimension "d26" = 6
  dimension "d27" = 6
  dimension "d28" = 6
  dimension "d29" = 6
  dimension "d30" = 6
  dimension "d31" = 7.5
  dimension "d32" = 2.5
  dimension "d34" = 360
  constraint coincident A0.centre A1.centre
  constraint collinear L0 L1
  constraint collinear L2 L3
  constraint concentric A2 A7
  constraint concentric A4 A9
  constraint concentric A2 A3
  constraint concentric A4 A5
  constraint concentric A6 A7
  constraint collinear L4 L5
  constraint collinear L6 L7
  constraint concentric A8 A9
  constraint tangent L4 A10
  constraint tangent A2 A10
  constraint tangent A3 A11
  constraint tangent L6 A11
  constraint tangent A2 A12
  constraint tangent L1 A12
  constraint tangent L3 A13
  constraint tangent A7 A13
  constraint tangent L5 A14
  constraint tangent A7 A14
  constraint tangent L7 A15
  constraint tangent A6 A15
  constraint tangent L2 A16
  constraint tangent A6 A16
  constraint tangent A3 A17
  constraint tangent L0 A17
  constraint tangent L6 A18
  constraint tangent A5 A18
  constraint tangent A5 A19
  constraint tangent L0 A19
  constraint tangent L2 A20
  constraint tangent A8 A20
  constraint tangent A8 A21
  constraint tangent L7 A21
  constraint tangent L4 A22
  constraint tangent A4 A22
  constraint tangent A4 A23
  constraint tangent L1 A23
  constraint tangent A9 A24
  constraint tangent L3 A24
  constraint tangent A9 A25
  constraint tangent L5 A25
  measures "d1" diameter of A0
  measures "d2" diameter of A2
  measures "d3" diameter of A1
  measures "d4" diameter of A4
  measures "d15" radius of A10
  measures "d16" radius of A11
  measures "d17" radius of A12
  measures "d18" radius of A13
  measures "d19" radius of A14
  measures "d20" radius of A15
  measures "d21" radius of A16
  measures "d22" radius of A17
  measures "d23" radius of A18
  measures "d24" radius of A19
  measures "d25" radius of A20
  measures "d26" radius of A21
  measures "d27" radius of A22
  measures "d28" radius of A23
  measures "d29" radius of A24
  measures "d30" radius of A25
  measures "d31" distance of A0.centre A26.centre
  measures "d32" diameter of A26
extrude "Extrude1" add sketch "Sketch1" along normal blind 5

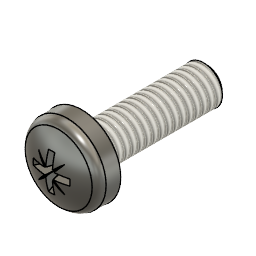
design "Pan Head Screw ISO 7045 - M2.5 x 8 - Z Steel 4.6 Plain"
description: Pan Head Screw ISO 7045 - M2.5 x 8 - Z
part number: ISO 7045 - M2.5 x 8 - Z Steel 4.6 Plain
Autodesk Fusion 360 part; units mm, degrees
sketch "Sketch1" plane through (0, 0, 0) normal (0, 1, 0) x (1, 0, 0)
  line L0 (-1.25, 0.9) -> (-1.25, 8)
  line L1 (-1.25, 8) -> (0, 8)
  line L2 (0, 8) -> (0, -2.1)
  line L3 (-1.1282, 0) -> (-2.5, 0)
  arc A0 (-2.4561, -1.2571) -> (0, -2.1) centre (0, 1.9) ccw
  line L4 (-1.25, 0.9) -> (-1.1282, 0.6388)
  line L5 (-1.1282, 0.6388) -> (-1.1282, 0)
  line L6 (-2.5, 0) -> (-2.4561, -1.2571)
  dimension "d9" = 2.5
  dimension "d75" = 5
  dimension "d98" = 2.2564
  dimension "d102" = 0.9
  dimension "d103" = 155
  dimension "d137" = 2
  dimension "d140" = 8
  dimension "d141" = 2.1
  constraint vertical L0
  constraint perpendicular L0 L1
  constraint coincident origin L3
  constraint coincident L2 A0.centre
  constraint vertical L2
  constraint vertical L5
  constraint coincident L3.start L5.end
  constraint coincident origin L2
  constraint perpendicular L3 L5
  constraint coincident A0.start L6.end
  measures "d102" distance of L3 L0.start
  measures "d103" angle of L4 L5
  measures "d137" angle of L2 L6
  measures "d140" distance of origin L1
  measures "d141" distance of L2.end L3
revolve "Revolve1" add sketch "Sketch1" angle 360 about axis through (0, 0, -8) along (0, 0, 1) makes body 1
ref_plane "WorkPlane1" through (0, 0, 2.1) normal (0, 0, 1) x (1, 0, 0)
sketch "Sketch7" plane through (0, 0, 2.1) normal (0, 0, 1) x (1, 0, 0)
  line L0 (0.258, -0.258) -> (0.258, 0.258)
  line L1 (0.258, 0.258) -> (-0.258, 0.258)
  line L2 (-0.258, 0.258) -> (-0.258, -0.258)
  line L3 (-0.258, -0.258) -> (0.258, -0.258)
  dimension "d150" = 0.516
  constraint vertical L0
  measures "d150" distance of L1 L3
extrude "Extrude4" add sketch "Sketch7" against normal blind 1.5 draft -10 separate body makes body 2
sketch "Sketch10" plane through (0, 0, 2.1) normal (0, 0, 1) x (1, 0, 0)
  line L0 (-0.215, 0.215) -> (-1.3, 0.215)
  line L1 (-1.3, 0.215) -> (-1.3, -0.215)
  line L2 (-1.3, -0.215) -> (-0.215, -0.215)
  line L3 (-0.215, -0.215) -> (-0.215, -1.3)
  line L4 (-0.215, -1.3) -> (0.215, -1.3)
  line L5 (0.215, -1.3) -> (0.215, -0.215)
  line L6 (0.215, -0.215) -> (1.3, -0.215)
  line L7 (1.3, -0.215) -> (1.3, 0.215)
  line L8 (1.3, 0.215) -> (0.215, 0.215)
  line L9 (0.215, 0.215) -> (0.215, 1.3)
  line L10 (0.215, 1.3) -> (-0.215, 1.3)
  line L11 (-0.215, 1.3) -> (-0.215, 0.215)
  dimension "d156" = 360
  dimension "d157" = 0.43
  dimension "d159" = 1.3
  constraint horizontal L0
  constraint perpendicular L0 L1
  constraint vertical L0.start L2.end
  constraint coincident L2.end L3.start
  measures "d157" distance of L0 L2
  measures "d159" distance of origin L1
extrude "Extrude1" add sketch "Sketch10" against normal blind 1.5 draft -6 separate body makes body 3
draft "Draft2" angle -30 neutral plane through (0, 0, 2.1) pull (0, 0, 1) 4 faces at (0.0191, -1.2474, 1.6) (-1.2474, 0.0191, 1.6) (1.2474, -0.0191, 1.6) (0.0191, 1.2474, 1.6) on bodies 3
combine "Combine1" operation cut target body 1 tool bodies 2 3
ref_plane "WorkPlane2" through (-1.1694, -0.1961, 1.9202) normal (0, 0, -1) x (-1, 0, 0)
sketch "Sketch8" plane through (-0.2873, 1.3933, 1.9202) normal (0, 0, -1) x (1, 0, 0)
  line L0 (0.2873, 1.3933) -> (1.2985, 2.4045)
  line L1 (2.0373, 1.3933) -> (22.7873, 1.3933)
  circle A0 centre (0.2873, 1.3933) radius 1.25
  line L2 (0.2873, 1.3933) -> (0.2873, 2.6433) construction
  line L3 (1.2985, 2.4045) -> (0.2873, 2.4045) construction
  point P0 (0.2873, 1.3933)
  dimension "d117" = 45
  dimension "d148" = 1.0112
  constraint coincident P0 L0.start
  constraint coincident A0 L2.end
  constraint vertical L2
  constraint coincident L2 L3.end
  constraint perpendicular L2 L3
  measures "d117" angle of L0 L1
  measures "d148" distance of P0 L3
ref_plane "WorkPlane3" through (0.5056, -0.5056, 1.9202) normal (-0.664463, -0.664463, 0.34202) x (0.707107, -0.707107, 0)
sketch "Sketch9" plane through (0.6856, -0.5201, 2.2417) normal (-0.664463, -0.664463, 0.34202) x (0.707107, -0.707107, 0)
  line L0 (-0.8525, -0.3422) -> (0.5775, -0.3422)
  line L1 (0.5775, -0.3422) -> (0.5775, 0.5178)
  line L2 (0.5775, 0.5178) -> (-0.8525, 0.5178)
  line L3 (-0.8525, 0.5178) -> (-0.8525, -0.3422)
  point P0 (-0.8525, -0.3422)
  point P1 (0.5775, -0.3422)
  dimension "d149" = 0.86
  constraint coincident P0 L0.start
  constraint coincident P1 L1
  constraint coincident P1 L0.end
  constraint vertical L1
  constraint vertical L3
  measures "d149" distance of L0 L2
extrude "Extrude6" cut sketch "Sketch9" along normal blind 0.215 draft -50 bodies 1
pattern_circular "C-Pattern1" count 4 over 360 about axis through (0, 0, 1.75) along (0, 0, 1) of "Extrude6"
fillet "Fillet4" radius 0.7 1 edges at (-2.2899, 0.8882, 1.2571) on bodies 1
thread "Thread1" "ISO Metric profile 2.5 M2.5x0.45 M2.5x0.45 6g" major diameter 2.43 minor diameter 1.9165 pitch 0.45 angle 60 resizes the face on face at (-1.2438, 0.1245, -5.6333) on bodies 1
fillet "Fillet5" radius 0.25 1 edges at (-1.0519, 0.408, 0) on bodies 1
sketch "Sketch5" plane through (0, 0, 0) normal (0, 1, 0) x (1, 0, 0)
  line L0 (-1.275, 8) -> (-1.275, 7.7239)
  line L1 (-1.275, 7.7239) -> (-0.9739, 8)
  line L2 (0, 8) -> (0, -2.1)
  line L3 (-1.275, 8) -> (0, 8)
  dimension "d114" = 1.275
  dimension "d143" = 0.2761
  dimension "d144" = 0.3011
  constraint coincident L2.start L3.end
  constraint perpendicular L2 L3
  constraint coincident L1.end L3
  constraint perpendicular L0 L3
  measures "d114" distance of origin L0
  measures "d143" distance of L0.end L3
  measures "d144" distance of L0 L1.end
revolve "Revolve2" cut sketch "Sketch5" angle 360 about axis through (0, 0, -8) along (0, 0, 1) bodies 1
equation "d9 = adsk_nomdia"
equation "adsk_nomlen = 8.00 mm"
equation "adsk_headh = 2.10 mm"
equation "adsk_headdia = 5.00 mm"
equation "adsk_nomdia = 2.50 mm"
equation "adsk_phildia = 2.60 mm"
equation "d31 = -adsk_phildepth"
equation "adsk_philwidth = 0.43 mm"
equation "adsk_phildepth = 1.50 mm"
equation "d68 = -adsk_phildepth"
equation "d75 = adsk_headdia"
equation "d79 = adsk_headh"
equation "d86 = adsk_philwidth / 2"
equation "adsk_thrlen = 7.10 mm"
equation "d98 = adsk_shnkdia"
equation "adsk_shnkdia = 2.25643 mm"
equation "d102 = adsk_nomlen - adsk_thrlen"
equation "adsk_endpointdia = 1.947895 mm"
equation "adsk_startlen = 0.276053 mm"
equation "d114 = adsk_nomdia * 0.51"
equation "adsk_ovalrad = 4.00 mm"
equation "adsk_headang = 2.00 deg"
equation "adsk_headtoprad = adsk_headh / 3"
equation "d132 = adsk_midfillet"
equation "adsk_midfillet = adsk_nomdia * 0.1"
equation "d136 = adsk_headtoprad"
equation "d137 = adsk_headang"
equation "d140 = adsk_nomlen"
equation "d141 = adsk_headh"
equation "d142 = ( adsk_nomlen + adsk_headh ) - ( adsk_ovalrad )"
equation "d143 = adsk_startlen"
equation "d144 = ( adsk_nomdia * 0.51 ) - ( adsk_endpointdia / 2 )"
equation "d148 = ( adsk_phildia / 2 * 1.1 ) * cos(45 deg)"
equation "d149 = adsk_philwidth * 2"
equation "d150 = adsk_philwidth * 1.2"
equation "d157 = adsk_philwidth"
equation "d159 = adsk_phildia / 2"

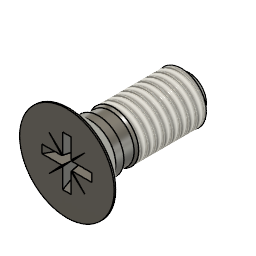
design "Countersunk Head Screw ISO 7046-2 - M5 x 12 - Z Steel 4.6 Plain"
description: Countersunk Head Screw ISO 7046-2 - M5 x 12 - Z
part number: ISO 7046-2 - M5x12 - Z Steel 4.6 Plain
Autodesk Fusion 360 part; units mm, degrees
sketch "Sketch1" plane through (0, 0, 0) normal (0, 1, 0) x (1, 0, 0)
  line L0 (0, -4.8) -> (-4.65, -4.8)
  line L1 (-4.65, -4.8) -> (-4.65, -4.65)
  line L2 (-4.65, -4.65) -> (-2.5, -2.5)
  line L3 (-2.5, -0.1) -> (-2.5, 7.2)
  line L4 (-2.5, 7.2) -> (0, 7.2)
  line L5 (0, 7.2) -> (0, -4.8)
  line L6 (-2.5, -0.1) -> (-2.3, -0.5)
  line L7 (-2.3, -0.5) -> (-2.3, -1.7)
  line L8 (-2.5, -2.5) -> (-2.5, -1.7)
  line L9 (-2.5, -1.7) -> (-2.3, -1.7)
  dimension "d9" = 5
  dimension "d11" = 9.3
  dimension "d89" = 4.6
  dimension "d90" = 5
  dimension "d91" = 0.8
  dimension "d93" = 7.3
  dimension "d120" = 12
  dimension "d126" = 45
  dimension "d127" = 7.7
  dimension "d131" = 0.15
  constraint perpendicular L0 L1
  constraint perpendicular L3 L4
  constraint perpendicular L0 L5
  constraint collinear origin L0.start L4.end
  constraint vertical L7
  constraint coincident origin L2
  constraint horizontal L9
  measures "d91" distance of L2.end L9
  measures "d93" distance of L4 L3.start
  measures "d120" distance of L0 L4
  measures "d126" angle of L2 L5
  measures "d127" distance of L4 L6.end
  measures "d131" distance of L0 L1.end
revolve "Revolve1" add sketch "Sketch1" angle 360 about axis through (0, 0, -7.2) along (0, 0, 1) makes body 1
sketch "Sketch7" plane through (0, 0, 4.8) normal (0, 0, 1) x (1, 0, 0)
  circle A0 centre (0, 0) radius 4.65
  line L0 (0.49, 0.49) -> (0.49, -0.49)
  line L1 (-0.49, 0.49) -> (0.49, 0.49)
  line L2 (-0.49, -0.49) -> (-0.49, 0.49)
  line L3 (0.49, -0.49) -> (-0.49, -0.49)
  dimension "d129" = 360
  dimension "d130" = 0.98
  constraint vertical L0
  constraint coincident L0.start L1.end
  measures "d130" distance of L1 L3
extrude "Extrude4" add sketch "Sketch7" against normal blind 2.44 draft -10 separate body contours L0 L1 L2 L3 makes body 2